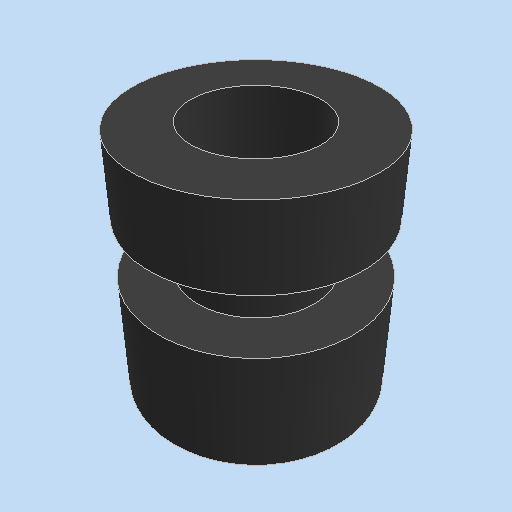
# Autodesk Inventor part: Antivibration_ball
Saved by Autodesk Inventor 2026 (Build 300175000, 175)
## iProperties
Created: 2026-10-09
Part Number: Antivibration_ball
Material: Generic
Document SubType Name: Modeling
Designer: Pacman Ng
Density: 1 g/cm^3
Appearance: Default
Author: Pacman Ng
Autodesk Inventor part; units mm, degrees
ref_plane "YZ Plane" through (0, 0, 0) normal (1, 0, 0) x (0, 1, 0)
ref_plane "XZ Plane" through (0, 0, 0) normal (0, 1, 0) x (-1, 0, 0)
ref_plane "XY Plane" through (0, 0, 0) normal (0, 0, 1) x (1, 0, 0)
sketch "Sketch1" plane through (0, 0, 0) normal (0, 1, 0) x (-1, 0, 0)
  line L0 (0, 0) -> (0, 6.5) construction
  line L1 (-1.6, 6.5) -> (-3, 6.5)
  line L2 (-3, 6.5) -> (-3, 4.5)
  line L3 (-1.6, 0) -> (-3, 0)
  line L4 (-3, 0) -> (-3, 3)
  line L5 (-1.8, 3) -> (-1.8, 4.5)
  line L6 (-3, 4.5) -> (-1.8, 4.5)
  line L7 (-3, 3) -> (-1.8, 3)
  line L8 (-1.6, 0) -> (-1.6, 6.5)
  point P0 (-1.8, 3.75)
  dimension "d0" = 6.5
  dimension "d1" = 3
  dimension "d2" = 2
  dimension "d3" = 3
  dimension "d4" = 3
  dimension "d6" = 1.8
  constraints: 18 end point, 4 vertical, 3 horizontal, 2 perpendicular, 1 midpoint
  measures "d0" distance of L0.start L0.end
  measures "d1" distance of L0.end L1.end
  measures "d2" distance of L1.end L2.end
  measures "d3" distance of L0.start L3.end
  measures "d4" distance of L3.end L4.end
  measures "d6" distance from line of point (-1.8, 3.75) L0
revolve "Revolution1" add sketch "Sketch1" angle 360 about axis through (0, 0, 0) along (0, 0, 1)
body "Solid1"
